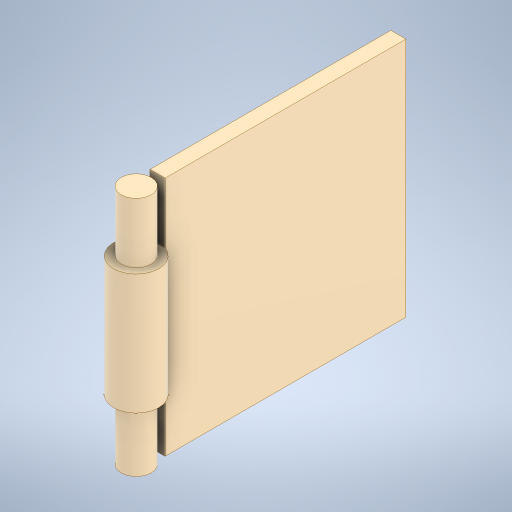
# Autodesk Inventor part: Door
Saved by Autodesk Inventor 2023 (Build 270158000, 158)
## iProperties
Created: 2024-03-28
Part Number: Door
Material: Polyethylene, Low Density
Document SubType Name: Modeling
Designer: BenFr
Density: 0.894 g/cm^3
Appearance: Smooth - Off-White
Mass: 37.6845 g
Surface Area: 174.882 cm^2
Volume: 42.1526 cm^3
Author: BenFr
Autodesk Inventor part; units mm, degrees
ref_plane "YZ Plane" through (0, 0, 0) normal (1, 0, 0) x (0, 1, 0)
ref_plane "XZ Plane" through (0, 0, 0) normal (0, 1, 0) x (-1, 0, 0)
ref_plane "XY Plane" through (0, 0, 0) normal (0, 0, 1) x (1, 0, 0)
sketch "Sketch1" plane through (0, 0, 0) normal (1, 0, 0) x (0, 1, 0)
  line L0 (0, 0) -> (20, 0)
  line L1 (20, 0) -> (60, 0)
  line L2 (60, 0) -> (80, 0)
  line L3 (60, -7.5) -> (20, -7.5)
  line L4 (20, -7.5) -> (20, -87.5)
  line L5 (20, -87.5) -> (60, -87.5)
  line L6 (60, -87.5) -> (60, -7.5)
  line L7 (0, -5) -> (20, -5)
  line L8 (20, -5) -> (20, -7.5)
  line L9 (60, -7.5) -> (60, -5)
  line L10 (60, -5) -> (80, -5)
  line L11 (80, -5) -> (80, 0)
  line L12 (0, -5) -> (0, 0)
  dimension "d0" = 20
  dimension "d1" = 40
  dimension "d2" = 20
  dimension "d3" = 80
  constraints: 26 end point, 4 horizontal, 3 parallel, 3 point on line, 2 perpendicular, 2 vertical
  measures "d0" distance of L0.start L0.end
  measures "d1" distance of L0.end L1.end
  measures "d2" distance of L1.end L2.end
  measures "d3" distance of L4.end L3.end
revolve "Revolution1" add sketch "Sketch1" angle 360 about axis through (0, 20, 0) along (0, 1, 0) contours L0 L1 L2 L11 L10 L9 L3 L8 L7 L12
ref_plane "Work Plane1" through (0, 20, 0) normal (0, 1, 0) x (1, 0, 0)
sketch "Sketch2" plane through (0, 20, 0) normal (0, 1, 0) x (1, 0, 0)
  circle A0 centre (0, 0) radius 7.5 projected
  line L0 (-2.5, 7.0711) -> (2.5, 7.0711)
  line L1 (2.5, 7.0711) -> (2.5, 87.0711)
  line L2 (2.5, 87.0711) -> (-2.5, 87.0711)
  line L3 (-2.5, 87.0711) -> (-2.5, 7.0711)
  dimension "d6" = 5
  dimension "d7" = 80
  constraints: 8 end point, 2 parallel, 1 horizontal, 1 perpendicular, 2 other
  measures "d6" distance of L2.end L1.end
  measures "d7" distance of L1.end L0.end
extrude "Extrusion1" add sketch "Sketch2" along normal blind 40 contours L0 A0 | A0 L3 L2 L1 picked at (0.2826, 7.198)
sketch "Sketch3" plane through (2.5, 20, -7.0711) normal (1, 0, 0) x (0, 0, -1)
  line L0 (0, 40) -> (-14.5711, 40) projected
  line L1 (0, 40) -> (80, 40)
  line L2 (80, 40) -> (80, 60)
  line L3 (80, 60) -> (0, 60)
  line L4 (0, 60) -> (0, 40)
  line L5 (0, 0) -> (80, 0) projected
  line L6 (0, 0) -> (80, 0)
  line L7 (80, 0) -> (80, -20)
  line L8 (80, -20) -> (0, -20)
  line L9 (0, -20) -> (0, 0)
  point P0 (-7.0711, -20)
  dimension "d10" = 80
  dimension "d11" = 20
  dimension "d12" = 80
  dimension "d13" = 20
  constraints: 16 end point, 4 parallel, 2 horizontal, 2 perpendicular
  measures "d10" distance of L3.end L2.end
  measures "d11" distance of L2.end L1.end
  measures "d12" distance of L7.end L8.end
  measures "d13" distance of L6.end L7.end
extrude "Extrusion2" add sketch "Sketch3" against normal blind 5
body "Solid1"
